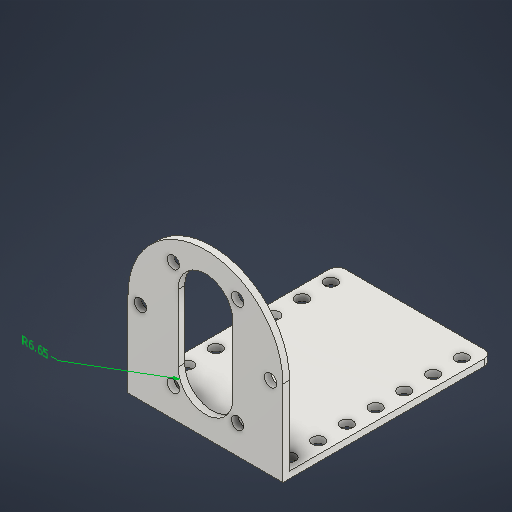
# Autodesk Inventor part: suporte_L_motor
Saved by Autodesk Inventor 2026 (Build 300175000, 175)
## iProperties
Created: 2025-04-24
Part Number: suporte_L_motor
Material: Genérico
Document SubType Name: Modeling
Designer: MARIA
Density: 1 g/cm^3
Appearance: Padrão
Author: MARIA
Autodesk Inventor part; units mm, degrees
ref_plane "YZ Plane" through (0, 0, 0) normal (1, 0, 0) x (0, 1, 0)
ref_plane "XZ Plane" through (0, 0, 0) normal (0, 1, 0) x (-1, 0, 0)
ref_plane "XY Plane" through (0, 0, 0) normal (0, 0, 1) x (1, 0, 0)
sketch "Esboço6" plane through (0, 0, 0) normal (0, 0, 1) x (1, 0, 0)
  line L0 (0, 0) -> (37.6, 0)
  line L1 (37.6, 0) -> (37.6, 20.7)
  line L2 (0, 0) -> (0, 20.7)
  arc A0 (37.6, 20.7) -> (0, 20.7) centre (18.8, 20.7) ccw
  point P0 (18.8, 39.5)
  dimension "d37" = 37.6
  dimension "d38" = 39.5
  constraints: 6 end point, 3 point on circle, 2 tangent, 1 centre point, 1 horizontal, 1 perpendicular, 1 vertical
  measures "d37" distance of L0.start L0.end
  measures "d38" distance from line of point (18.8, 39.5) L0
extrude "Extrusão3" add sketch "Esboço6" against normal blind 1.6
sketch "Esboço8" plane through (0, 0, -1.6) normal (0, 0, -1) x (-1, 0, 0)
  line L0 (-37.6, 0) -> (0, 0) projected
  line L1 (-37.6, 20.7) -> (-37.6, 0) projected
  line L2 (0, 0) -> (-37.6, 0)
  line L3 (-37.6, 0) -> (-37.6, 1.6)
  line L4 (-37.6, 1.6) -> (0, 1.6)
  line L5 (0, 1.6) -> (0, 0)
  dimension "d44" = 1.6
  constraints: 8 end point, 2 parallel, 1 horizontal, 1 perpendicular, 1 point on line
  measures "d44" distance of L4.end L0.end
extrude "Extrusão5" add sketch "Esboço8" along normal blind 49.2
sketch "Esboço9" plane through (0, 1.6, -1.6) normal (0, 1, 0) x (1, 0, 0)
  circle A0 centre (2.9, 44.7) radius 1.5
  line L0 (0, 49.2) -> (37.6, 49.2) projected
  line L1 (0, 0) -> (0, 49.2) projected
  point P0 (0, -1.6)
  dimension "d47" = 3
  dimension "d48" = 4.5
  dimension "d49" = 2.9
  constraints: 1 centre point
  measures "d47" diameter of A0
  measures "d48" distance from line of L0 A0.centre
  measures "d49" distance from line of L1 A0.centre
hole "Furo2" at (2.9, 1.6, -46.3) direction (0, -1, 0) diameter 3 end through all
pattern_linear "Padrão retangular3" count 7 spacing 6.97 along (0, 0, 1) count 2 spacing 31.8 along (1, 0, 0) of "Furo2"
fillet "Arredondamento2" radius 2 2 edges at (37.6, 0.8, -50.8) (0, 0.8, -50.8)
sketch "Esboço10" plane through (0, 0, 0) normal (0, 0, 1) x (1, 0, 0)
  line L0 (12.15, 27.85) -> (12.15, 11.55)
  arc A0 (12.15, 11.55) -> (25.45, 11.55) centre (18.8, 11.55) ccw
  arc A1 (25.45, 27.85) -> (12.15, 27.85) centre (18.8, 27.85) ccw
  line L1 (25.45, 27.85) -> (25.45, 11.55)
  arc A2 (37.6, 20.7) -> (0, 20.7) centre (18.8, 20.7) ccw projected
  line L2 (18.8, 39.5) -> (18.8, 0)
  line L3 (37.6, 0) -> (37.6, 20.7) projected
  point P0 (0, 0)
  point P1 (18.8, 39.5)
  point P2 (18.8, 34.5)
  dimension "d64" = 18.8
  dimension "d66" = 13.3
  dimension "d67" = 5
  dimension "d68" = 16.3
  constraints: 7 point on circle, 6 end point, 4 tangent, 3 vertical, 2 centre point, 1 point on line
  measures "d64" distance between parallel lines of L3 L2
  measures "d66" distance between parallel lines of L1 L0
  measures "d67" distance of point (18.8, 39.5) point (18.8, 34.5)
  measures "d68" distance of A0.centre A1.centre
extrude "Extrusão6" cut sketch "Esboço10" against normal through all
sketch "Esboço11" plane through (0, 0, 0) normal (0, 0, 1) x (1, 0, 0)
  circle A0 centre (11, 33) radius 1.5
  arc A1 (37.6, 20.7) -> (0, 20.7) centre (18.8, 20.7) ccw projected
  arc A2 (25.45, 27.85) -> (12.15, 27.85) centre (18.8, 27.85) ccw projected
  circle A3 centre (3, 20) radius 1.5
  circle A4 centre (11, 7) radius 1.5
  line L0 (0, 20.7) -> (0, 0) projected
  arc A5 (12.15, 11.55) -> (25.45, 11.55) centre (18.8, 11.55) ccw projected
  line L1 (18.8, 27.85) -> (18.8, 11.55)
  circle A6 centre (26.6, 33) radius 1.5
  circle A7 centre (34.6, 20) radius 1.5
  circle A8 centre (26.6, 7) radius 1.5
  dimension "d72" = 3
  dimension "d73" = 12.3
  dimension "d74" = 7.8
  dimension "d75" = 3
  dimension "d76" = 13
  dimension "d77" = 11
  dimension "d78" = 4.55
  constraints: 6 centre point, 3 symmetric about line, 2 end point, 2 equal radius, 1 vertical, 3 other
  measures "d72" diameter of A0
  measures "d73" vertical distance of A1.centre A0.centre
  measures "d74" horizontal distance of L1.start A0.centre
  measures "d75" distance from line of L0 A3.centre
  measures "d76" vertical distance of A0.centre A3.centre
  measures "d77" distance from line of L0 A4.centre
  measures "d78" vertical distance of L1.end A4.centre
extrude "Extrusão7" cut sketch "Esboço11" against normal through all
